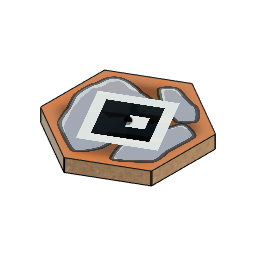
TABLE_2022 (Autodesk Fusion 360 archive; units mm, degrees)
design "EchantillonBleu"
Autodesk Fusion 360 part; units mm, degrees
sketch "Sketch1" plane through (0, 0, 0) normal (0, 0, 1) x (1, 0, 0)
  line L0 (64.9519, 37.5) -> (0, 75)
  line L1 (0, 75) -> (-64.9519, 37.5)
  line L2 (-64.9519, 37.5) -> (-64.9519, -37.5)
  line L3 (-64.9519, -37.5) -> (0, -75)
  line L4 (0, -75) -> (64.9519, -37.5)
  line L5 (64.9519, -37.5) -> (64.9519, 37.5)
  dimension "d3" = 75
  constraint vertical L5
  measures "d3" distance of L0.end origin
extrude "Extrude1" add sketch "Sketch1" along normal blind 15
fillet "Congé1" radius 1 6 edges at (-64.9519, -37.5, 7.5) (0, -75, 7.5) (64.9519, -37.5, 7.5) (64.9519, 37.5, 7.5) (0, 75, 7.5) (-64.9519, 37.5, 7.5)
sketch "Esquisse2" plane through (0, 0, 15) normal (0, 0, 1) x (-1, 0, 0)
  arc A0 (64.4519, -37.7887) -> (64.9519, -36.9226) centre (63.9519, -36.9226) ccw
  line L0 (64.9519, -36.9226) -> (64.9519, 36.9226)
  arc A1 (64.9519, 36.9226) -> (64.4519, 37.7887) centre (63.9519, 36.9226) ccw
  line L1 (64.4519, 37.7887) -> (0.5, 74.7113)
  arc A2 (0.5, 74.7113) -> (-0.5, 74.7113) centre (0, 73.8453) ccw
  line L2 (-0.5, 74.7113) -> (-64.4519, 37.7887)
  arc A3 (-64.4519, 37.7887) -> (-64.9519, 36.9226) centre (-63.9519, 36.9226) ccw
  line L3 (-64.9519, 36.9226) -> (-64.9519, -36.9226)
  arc A4 (-64.9519, -36.9226) -> (-64.4519, -37.7887) centre (-63.9519, -36.9226) ccw
  line L4 (-64.4519, -37.7887) -> (-0.5, -74.7113)
  arc A5 (-0.5, -74.7113) -> (0.5, -74.7113) centre (0, -73.8453) ccw
  line L5 (0.5, -74.7113) -> (64.4519, -37.7887)
equation "diaEchantillon = 150 mm"
equation "epEchantillon = 15 mm"
equation "d3 = diaEchantillon / 2"
equation "d4 = epEchantillon"

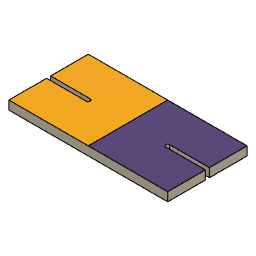
design "MiddleBeaconTop"
Autodesk Fusion 360 part; units mm, degrees
ref_plane "WorkPlane1" through (0, 1000, 0) normal (0, 1, 0) x (0, 0, 1)
sketch "Sketch1" plane through (0, 1000, 0) normal (0, 1, 0) x (1, 0, 0)
  line L0 (-200, -100) -> (200, -100)
  line L1 (200, -100) -> (200, 100)
  line L2 (200, 100) -> (-200, 100)
  line L3 (-200, 100) -> (-200, -100)
  line L4 (-200, -100) -> (200, 100) construction
  line L5 (200, -100) -> (-200, 100) construction
  line L6 (-200, -5) -> (-100, -5)
  arc A0 (-100, -5) -> (-100, 5) centre (-100, 0) ccw
  line L7 (-100, 5) -> (-200, 5)
  arc A1 (-200, 5) -> (-200, -5) centre (-200, 0) ccw
  line L8 (-200, 0) -> (-100, 0) construction
  line L9 (200, 5) -> (100, 5)
  arc A2 (100, 5) -> (100, -5) centre (100, 0) ccw
  line L10 (100, -5) -> (200, -5)
  arc A3 (200, -5) -> (200, 5) centre (200, 0) ccw
  line L11 (200, 0) -> (100, 0) construction
  dimension "d2" = 400
  dimension "d3" = 200
  dimension "d4" = 100
  dimension "d5" = 5
  constraint perpendicular L0 L1
  constraint parallel L0 L2
  constraint parallel L1 L3
  constraint horizontal L0
  constraint coincident L4 origin
  constraint coincident L5 origin
  constraint tangent L6 A0
  constraint tangent A0 L7
  constraint parallel L6 L7
  constraint tangent L7 A1
  constraint tangent L6 A1
  constraint perpendicular L3 L8
  constraint midpoint L3 A1.centre
  constraint tangent L9 A2
  constraint tangent A2 L10
  constraint parallel L9 L10
  constraint tangent L10 A3
  constraint tangent L9 A3
  constraint perpendicular L1 L11
  constraint midpoint L1 A3.centre
  constraint equal A0 A2
  constraint equal L8 L11
  measures "d2" distance of L1.end L2.end
  measures "d3" distance of L0.end L1.end
  measures "d4" distance of A1.centre A0.centre
  measures "d5" radius of A0
extrude "Extrude1" add sketch "Sketch1" against normal blind 22 contours L0 L1 L2 L3 L6 A0 L7 L9 A2 L10
ref_plane "WorkPlane2" through (0, 989, 52.5) normal (1, 0, 0) x (0, 0, 1)
split_face "SplitFace1" 1 faces at (-32.5, 1000, 68.11) by plane through (0, 989, 52.5) normal (1, 0, 0)

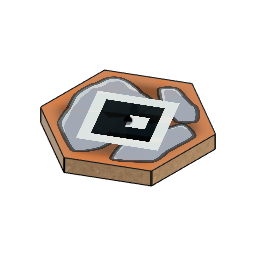
design "EchantillonRouge"
Autodesk Fusion 360 part; units mm, degrees
sketch "Sketch1" plane through (0, 0, 0) normal (0, 0, 1) x (1, 0, 0)
  line L0 (64.9519, 37.5) -> (0, 75)
  line L1 (0, 75) -> (-64.9519, 37.5)
  line L2 (-64.9519, 37.5) -> (-64.9519, -37.5)
  line L3 (-64.9519, -37.5) -> (0, -75)
  line L4 (0, -75) -> (64.9519, -37.5)
  line L5 (64.9519, -37.5) -> (64.9519, 37.5)
  dimension "d3" = 75
  constraint vertical L5
  measures "d3" distance of L0.end origin
extrude "Extrude1" add sketch "Sketch1" along normal blind 15
fillet "Congé1" radius 1 6 edges at (-64.9519, -37.5, 7.5) (0, -75, 7.5) (64.9519, -37.5, 7.5) (64.9519, 37.5, 7.5) (0, 75, 7.5) (-64.9519, 37.5, 7.5)
sketch "Esquisse2" plane through (0, 0, 15) normal (0, 0, 1) x (-1, 0, 0)
  arc A0 (64.4519, -37.7887) -> (64.9519, -36.9226) centre (63.9519, -36.9226) ccw
  line L0 (64.9519, -36.9226) -> (64.9519, 36.9226)
  arc A1 (64.9519, 36.9226) -> (64.4519, 37.7887) centre (63.9519, 36.9226) ccw
  line L1 (64.4519, 37.7887) -> (0.5, 74.7113)
  arc A2 (0.5, 74.7113) -> (-0.5, 74.7113) centre (0, 73.8453) ccw
  line L2 (-0.5, 74.7113) -> (-64.4519, 37.7887)
  arc A3 (-64.4519, 37.7887) -> (-64.9519, 36.9226) centre (-63.9519, 36.9226) ccw
  line L3 (-64.9519, 36.9226) -> (-64.9519, -36.9226)
  arc A4 (-64.9519, -36.9226) -> (-64.4519, -37.7887) centre (-63.9519, -36.9226) ccw
  line L4 (-64.4519, -37.7887) -> (-0.5, -74.7113)
  arc A5 (-0.5, -74.7113) -> (0.5, -74.7113) centre (0, -73.8453) ccw
  line L5 (0.5, -74.7113) -> (64.4519, -37.7887)
equation "diaEchantillon = 150 mm"
equation "epEchantillon = 15 mm"
equation "d3 = diaEchantillon / 2"
equation "d4 = epEchantillon"

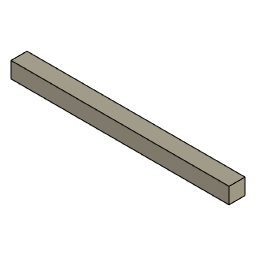
design "BarreSeparation"
Autodesk Fusion 360 part; units mm, degrees
sketch "Sketch1" plane through (0, 0, 0) normal (1, 0, 0) x (0, 1, 0)
  line L0 (11, 0) -> (-11, 0)
  line L1 (-11, 0) -> (-11, 22)
  line L2 (-11, 22) -> (11, 22)
  line L3 (11, 22) -> (11, 0)
  line L4 (11, 0) -> (-11, 22) construction
  line L5 (-11, 0) -> (11, 22) construction
  point P0 (0, 11)
  dimension "d1" = 22
  constraint horizontal L0
  constraint perpendicular L0 L1
  constraint parallel L0 L2
  constraint parallel L1 L3
  constraint coincident L4 P0
  constraint coincident L5 P0
  constraint midpoint origin L0
  constraint equal L2 L3
  measures "d1" distance of L1.end L2.end
extrude "Extrude1" add sketch "Sketch1" along normal blind 300

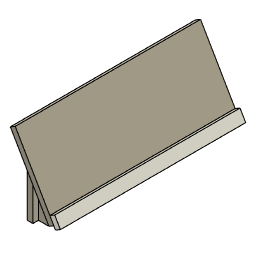
design "Frise"
Autodesk Fusion 360 part; units mm, degrees
sketch "Sketch1" plane through (0, 0, 0) normal (1, 0, 0) x (0, 1, 0)
  line L0 (-600, 70) -> (600, 70)
  line L1 (600, 70) -> (600, 0)
  line L2 (600, 0) -> (-600, 0)
  line L3 (-600, 0) -> (-600, 70)
  dimension "d1" = 70
  dimension "d2" = 1200
  constraint horizontal L0
  constraint vertical L1
  constraint horizontal L2
  constraint vertical L3
  constraint midpoint origin L2
  measures "d1" distance of L0.end L1.end
  measures "d2" distance of L0.start L0.end
extrude "Extrude1" add sketch "Sketch1" against normal blind 22 makes body 1 in component "TERRAIN (A ENLEVER)"
sketch "Sketch2" plane through (0, 0, 0) normal (0, 0, -1) x (1, 0, 0)
  line L0 (0, -600) -> (0, 600)
  line L1 (0, 600) -> (-22, 600)
  line L2 (-22, 600) -> (-22, -600)
  line L3 (-22, -600) -> (0, -600)
  line L4 (-22, 600) -> (978, 600)
  line L5 (978, 600) -> (978, -600)
  line L6 (978, -600) -> (-22, -600)
  line L7 (-22, -600) -> (-22, 600)
  dimension "d5" = 1000
  constraint horizontal L4
  constraint vertical L5
  constraint horizontal L6
  constraint vertical L7
  constraint coincident L1.end L2.start
  constraint coincident L0.start L6
  measures "d5" distance of L1.end L4.end
extrude "Extrude2" add sketch "Sketch2" along normal blind 22 bodies 1 in component "TERRAIN (A ENLEVER)"
sketch "Sketch3" plane through (0, 0, 0) normal (0, 1, 0) x (1, 0, 0)
  line L0 (0, 0) -> (0, -70)
  line L1 (0, -70) -> (40.4145, 0)
  line L2 (40.4145, 0) -> (0, 0)
  line L3 (0, -70) -> (0, -75.899) construction
  line L4 (0, -75.899) -> (0, -118.8533) construction
  line L5 (40.4145, 0) -> (59.4671, -11)
  line L6 (59.4671, -11) -> (-90.5329, -270.8076)
  line L7 (-90.5329, -270.8076) -> (-109.5855, -259.8076)
  line L8 (-109.5855, -259.8076) -> (40.4145, 0)
  line L9 (59.4671, -11) -> (78.5196, -22)
  line L10 (78.5196, -22) -> (62.8696, -49.1066)
  line L11 (62.8696, -49.1066) -> (43.8171, -38.1066)
  line L12 (43.8171, -38.1066) -> (59.4671, -11)
  dimension "d10" = 70
  dimension "d13" = 30
  dimension "d14" = 22
  dimension "d15" = 300
  dimension "d18" = 22
  dimension "d19" = 31.3
  constraint coincident L0.start L2.end
  constraint vertical L0
  constraint perpendicular L0 L2
  constraint parallel L0 L4
  constraint perpendicular L5 L6
  constraint parallel L5 L7
  constraint parallel L6 L8
  constraint perpendicular L1 L5
  constraint perpendicular L9 L10
  constraint parallel L9 L11
  constraint parallel L10 L12
  constraint perpendicular L6 L9
  measures "d10" distance of L0.start L0.end
  measures "d13" angle of L1 L4
  measures "d14" distance of L1.end L5.end
  measures "d15" distance of L5.end L6.end
  measures "d18" distance of L10.end L11.end
  measures "d19" distance of L9.end L10.end
extrude "Extrude1'" add sketch "Sketch3" along normal mid plane 720 separate body contours L1 L5 L6 L7 L8 L12 makes body 2 in component "FRISE"
extrude "Extrude1''" add sketch "Sketch3" along normal mid plane 720 separate body contours L6 L9 L10 L11 L12 makes body 3 in component "BORDURE"
extrude "Extrude1'''" add sketch "Sketch3" along normal blind 22 from surface at -360 separate body contours L0 L1 L2 L8 makes body 4 in component "TRIANGLE_GAUCHE"
extrude "Extrude1''''" add sketch "Sketch3" against normal blind 22 from surface at 360 separate body contours L0 L1 L2 L8 makes body 5 in component "TRIANGLE_DROIT"
extrude "Extrude1'''''" add sketch "Sketch3" along normal mid plane 22 separate body contours L0 L1 L2 L8 makes body 6 in component "TRIANGLE_CENTRE"
sketch "Esquisse1" plane through (0, -360, 0) normal (0, -1, 0) x (1, 0, 0) in component "BORDURE"
  line L0 (62.8696, 49.1066) -> (43.8171, 38.1066)
  line L1 (43.8171, 38.1066) -> (59.4671, 11)
  line L2 (59.4671, 11) -> (78.5196, 22)
  line L3 (78.5196, 22) -> (62.8696, 49.1066)
  line L4 (59.4671, 11) -> (65.8179, 0)
  line L5 (65.8179, 0) -> (84.8705, 11)
  line L6 (84.8705, 11) -> (78.5196, 22)
  line L7 (40.4145, 0) -> (0, 0)
  constraint coincident L1.end L2.start
  constraint perpendicular L2 L4
  constraint perpendicular L1 L5
  constraint coincident L2.end L3.start
  constraint perpendicular L5 L6
  constraint coincident L4.end L7
extrude "Extrusion2" add sketch "Esquisse1" against normal blind 720 contours L2 L4 L5 L6 bodies 3 in component "BORDURE"
sketch "Esquisse1 (2)" plane through (0, -360, 0) normal (0, -1, 0) x (1, 0, 0) in component "TaquetArriere"
  line L0 (40.4145, 0) -> (0, 70)
  line L1 (0, 70) -> (0, 0)
  line L2 (0, 0) -> (40.4145, 0)
  line L3 (-22, 0) -> (-22, 108.1051)
  line L4 (-22, 108.1051) -> (-44, 146.2102)
  line L5 (-44, 146.2102) -> (-44, 0)
  line L6 (-44, 0) -> (-22, 0)
  line L7 (-109.5855, 259.8076) -> (40.4145, 0)
  dimension "d152" = 22
  dimension "d153" = 22
  constraint vertical L3
  constraint parallel L3 L5
  constraint perpendicular L3 L6
  constraint coincident L3.end L7
  constraint coincident L4.end L7
  constraint collinear L2 L6
  measures "d152" distance of L1 L3
  measures "d153" distance of L3.start L5.end
extrude "Extrusion1" add sketch "Esquisse1 (2)" against normal blind 22 separate body contours L3 L4 L5 L6 L7 makes body 7 in component "TaquetArriere"
extrude "Extrusion2'" add 1 faces at (-36.6667, -352.6667, 0) along direction (0, 0, -1) blind 22 on bodies 7 bodies 7 in component "TaquetArriere"
component "TERRAIN (A ENLEVER)" placed x (1, 0, 0) y (0, 1, 0) z (0, 0, 1) at (0, 0, 0)
component "FRISE" placed x (1, 0, 0) y (0, 1, 0) z (0, 0, 1) at (0, 0, 0)
component "BORDURE" placed x (1, 0, 0) y (0, 1, 0) z (0, 0, 1) at (0, 0, 0)
component "TRIANGLE_GAUCHE" placed x (1, 0, 0) y (0, 1, 0) z (0, 0, 1) at (0, 0, 0)
component "TRIANGLE_DROIT" placed x (1, 0, 0) y (0, 1, 0) z (0, 0, 1) at (0, 0, 0)
component "TRIANGLE_CENTRE" placed x (1, 0, 0) y (0, 1, 0) z (0, 0, 1) at (0, 0, 0)
component "TaquetArriere" placed x (1, 0, 0) y (0, 1, 0) z (0, 0, 1) at (0, 0, 0)
component "TaquetArriere" placed x (1, 0, 0) y (0, 1, 0) z (0, 0, 1) at (0, 698, 0)
component "TaquetArriere" placed x (1, 0, 0) y (0, 1, 0) z (0, 0, 1) at (0, 349, 0)
equation "hauteurFrise = 300 mm"
equation "largeurFrise = 720 mm"
equation "angleFrise = 30 deg"
equation "epaisseurFrise = 22 mm"
equation "d13 = angleFrise"
equation "d14 = epaisseurFrise"
equation "d15 = hauteurFrise"
equation "d16 = largeurFrise / 2"
equation "d18 = epaisseurFrise"
equation "d20 = largeurFrise"
equation "d23 = epaisseurFrise"
equation "d26 = -epaisseurFrise"
equation "d28 = epaisseurFrise"
equation "d62 = 180 deg + angleFrise"

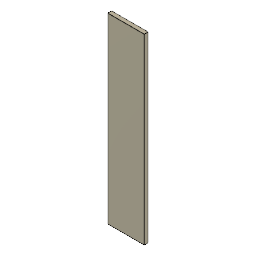
design "MiddleBeaconVertSupport2"
Autodesk Fusion 360 part; units mm, degrees
sketch "Sketch1" plane through (0, 0, 0) normal (0, 0, 1) x (1, 0, 0)
  line L0 (-200, 1000) -> (0, 1000)
  line L1 (0, 1000) -> (0, 0)
  line L2 (0, 0) -> (-200, 0)
  line L3 (-200, 0) -> (-200, 1000)
  dimension "d1" = 1000
  dimension "d2" = 200
  measures "d1" distance of L1.end
extrude "Extrude1" add sketch "Sketch1" along normal mid plane 22

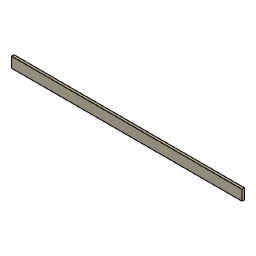
design "BorderSmall"
Autodesk Fusion 360 part; units mm, degrees
sketch "Sketch1" plane through (0, 0, 0) normal (0, 0, 1) x (1, 0, 0)
  line L0 (0, 0) -> (2044, 0)
  line L1 (2044, 0) -> (2044, 92)
  line L2 (2044, 92) -> (0, 92)
  line L3 (0, 92) -> (0, 0)
  dimension "d1" = 2044
  dimension "d2" = 92
  constraint horizontal L0
  constraint vertical L1
  constraint horizontal L2
  constraint vertical L3
  constraint coincident L0.start L3.end
  measures "d1" distance of L0.start L0.end
  measures "d2" distance of L0.start L2.end
extrude "Extrude1" add sketch "Sketch1" along normal blind 22
equation "d1 = 2000 mm + 44 mm"
equation "d2 = 70 mm + 22 mm"
equation "d7 = 22 mm + 400 mm"

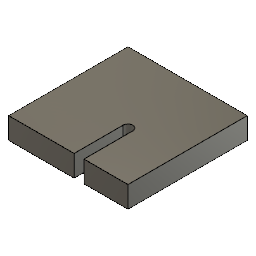
design "EdgeBeacons_Base"
Autodesk Fusion 360 part; units mm, degrees
sketch "Sketch1" plane through (0, 0, 0) normal (0, 1, 0) x (1, 0, 0)
  line L0 (-61, 61) -> (61, 61)
  line L1 (61, 61) -> (61, -61)
  line L2 (-61, -61) -> (-61, 61)
  line L3 (-61, 61) -> (61, -61) construction
  line L4 (16, -61) -> (16, -11)
  arc A0 (16, -11) -> (6, -11) centre (11, -11) ccw
  line L5 (6, -11) -> (6, -61)
  line L6 (11, -61) -> (11, -11) construction
  line L7 (61, -61) -> (16, -61)
  line L8 (6, -61) -> (-61, -61)
  dimension "d1" = 122
  dimension "d4" = 50
  dimension "d5" = 10
  dimension "d6" = 50
  measures "d1" distance of L0.start L0.end
  measures "d4" distance of L6.start A0.centre
  measures "d5" diameter of A0
  measures "d6" distance of L1 L6
extrude "Extrude1" add sketch "Sketch1" along normal blind 22

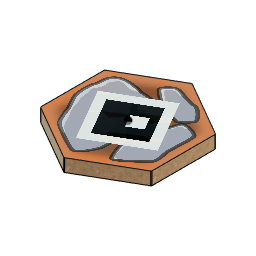
design "EchantillonVert"
Autodesk Fusion 360 part; units mm, degrees
sketch "Sketch1" plane through (0, 0, 0) normal (0, 0, 1) x (1, 0, 0)
  line L0 (64.9519, 37.5) -> (0, 75)
  line L1 (0, 75) -> (-64.9519, 37.5)
  line L2 (-64.9519, 37.5) -> (-64.9519, -37.5)
  line L3 (-64.9519, -37.5) -> (0, -75)
  line L4 (0, -75) -> (64.9519, -37.5)
  line L5 (64.9519, -37.5) -> (64.9519, 37.5)
  dimension "d3" = 75
  constraint vertical L5
  measures "d3" distance of L0.end origin
extrude "Extrude1" add sketch "Sketch1" along normal blind 15
fillet "Congé1" radius 1 6 edges at (-64.9519, -37.5, 7.5) (0, -75, 7.5) (64.9519, -37.5, 7.5) (64.9519, 37.5, 7.5) (0, 75, 7.5) (-64.9519, 37.5, 7.5)
sketch "Esquisse2" plane through (0, 0, 15) normal (0, 0, 1) x (-1, 0, 0)
  arc A0 (64.4519, -37.7887) -> (64.9519, -36.9226) centre (63.9519, -36.9226) ccw
  line L0 (64.9519, -36.9226) -> (64.9519, 36.9226)
  arc A1 (64.9519, 36.9226) -> (64.4519, 37.7887) centre (63.9519, 36.9226) ccw
  line L1 (64.4519, 37.7887) -> (0.5, 74.7113)
  arc A2 (0.5, 74.7113) -> (-0.5, 74.7113) centre (0, 73.8453) ccw
  line L2 (-0.5, 74.7113) -> (-64.4519, 37.7887)
  arc A3 (-64.4519, 37.7887) -> (-64.9519, 36.9226) centre (-63.9519, 36.9226) ccw
  line L3 (-64.9519, 36.9226) -> (-64.9519, -36.9226)
  arc A4 (-64.9519, -36.9226) -> (-64.4519, -37.7887) centre (-63.9519, -36.9226) ccw
  line L4 (-64.4519, -37.7887) -> (-0.5, -74.7113)
  arc A5 (-0.5, -74.7113) -> (0.5, -74.7113) centre (0, -73.8453) ccw
  line L5 (0.5, -74.7113) -> (64.4519, -37.7887)
equation "diaEchantillon = 150 mm"
equation "epEchantillon = 15 mm"
equation "d3 = diaEchantillon / 2"
equation "d4 = epEchantillon"

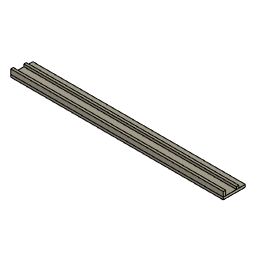
design "SupportCarreFouille"
Autodesk Fusion 360 part; units mm, degrees
sketch "Esquisse1" plane through (0, 0, 0) normal (1, 0, 0) x (0, 1, 0)
  line L0 (0, 0) -> (202, 0)
  line L1 (202, 0) -> (202, 22)
  line L2 (202, 22) -> (0, 22)
  line L3 (0, 22) -> (0, 0)
  line L4 (0, 22) -> (0, 66)
  line L5 (0, 66) -> (22, 66)
  line L6 (22, 66) -> (22, 22)
  line L7 (121, 22) -> (121, 44)
  line L8 (121, 44) -> (143, 44)
  line L9 (143, 44) -> (143, 22)
  dimension "d1" = 22
  dimension "d3" = 22
  dimension "d4" = 44
  dimension "d5" = 22
  dimension "d6" = 22
  dimension "d8" = 59
  dimension "d9" = 180
  constraint coincident L0.start L3.end
  constraint horizontal L0
  constraint perpendicular L0 L1
  constraint perpendicular L1 L2
  constraint perpendicular L0 L3
  constraint perpendicular L2 L4
  constraint perpendicular L3 L5
  constraint coincident L2 L6.end
  constraint perpendicular L2 L6
  constraint coincident L2 L7.start
  constraint perpendicular L2 L7
  constraint perpendicular L7 L8
  constraint coincident L2 L9.end
  constraint perpendicular L2 L9
  measures "d1" distance of L0 L2
  measures "d3" distance of L4.end L5.end
  measures "d4" distance of L2.end L4.end
  measures "d5" distance of L7.end L8.end
  measures "d6" distance of L7.start L7.end
  measures "d8" distance of L1 L9
  measures "d9" distance of L1 L6
extrude "Extrusion1" add sketch "Esquisse1" along normal mid plane 1950 contours L0 L1 L2 L3 makes body 1
extrude "Extrusion2" add sketch "Esquisse1" along normal mid plane 1950 separate body contours L2 L4 L5 L6 makes body 2
extrude "Extrusion3" add sketch "Esquisse1" along normal mid plane 1950 separate body contours L2 L7 L8 L9 makes body 3
equation "d10 = ( 1950 / 2 ) * 1 mm"
equation "d12 = ( 1950 / 2 ) * 1 mm"
equation "d14 = ( 1950 / 2 ) * 1 mm"

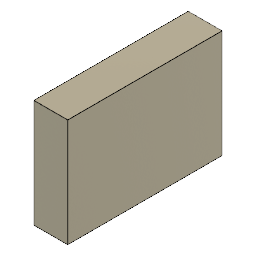
design "EdgeBeacons_SmallBorder"
Autodesk Fusion 360 part; units mm, degrees
sketch "Sketch1" plane through (0, 0, 0) normal (1, 0, 0) x (0, 0, -1)
  line L0 (0, 70) -> (100, 70)
  line L1 (100, 70) -> (100, 0)
  line L2 (100, 0) -> (0, 0)
  line L3 (0, 0) -> (0, 70)
  dimension "d1" = 70
  dimension "d2" = 100
  constraint horizontal L0
  constraint vertical L1
  constraint horizontal L2
  constraint vertical L3
  constraint coincident L2.end L3.start
  measures "d1" distance of L0.start L2.end
  measures "d2" distance of L0.start L0.end
extrude "Extrude1" add sketch "Sketch1" along normal blind 22
equation "d1 = 48 mm + 22 mm"
equation "d2 = 122 mm - 22 mm"

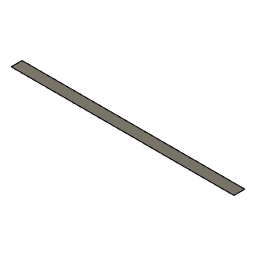
design "PaintExperience"
Autodesk Fusion 360 part; units mm, degrees
sketch "Sketch1" plane through (0, 0, 0) normal (0, 1, 0) x (1, 0, 0)
  line L0 (0, 0) -> (450, 0)
  line L1 (450, 0) -> (450, -22)
  line L2 (450, -22) -> (0, -22)
  line L3 (0, -22) -> (0, 0)
  dimension "d1" = 450
  dimension "d2" = 22
  constraint horizontal L0
  constraint vertical L1
  constraint horizontal L2
  constraint vertical L3
  constraint coincident L0.start L3.end
  measures "d1" distance of L0.start L0.end
  measures "d2" distance of L0.start L2.end
extrude "Extrude1" add sketch "Sketch1" along normal blind 0.1

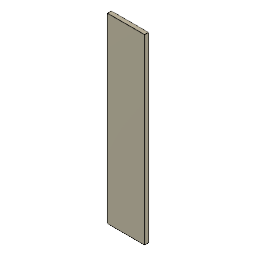
design "MiddleBeaconVertSupport1"
Autodesk Fusion 360 part; units mm, degrees
sketch "Sketch1" plane through (0, 0, 0) normal (0, 0, 1) x (1, 0, 0)
  line L0 (-200, 978) -> (0, 978)
  line L1 (0, 978) -> (0, 0)
  line L2 (0, 0) -> (-200, 0)
  line L3 (-200, 0) -> (-200, 978)
  dimension "d1" = 978
  dimension "d2" = 200
  measures "d1" distance of L1.end
extrude "Extrude1" add sketch "Sketch1" along normal mid plane 22
equation "d1 = 1000 mm - 22 mm"

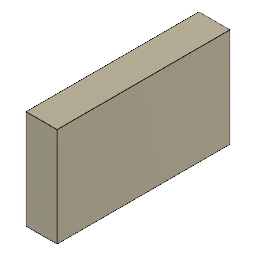
design "EdgeBeacons_LargeBorder"
Autodesk Fusion 360 part; units mm, degrees
sketch "Sketch1" plane through (0, 0, 0) normal (1, 0, 0) x (0, 0, -1)
  line L0 (0, 70) -> (122, 70)
  line L1 (122, 70) -> (122, 0)
  line L2 (122, 0) -> (0, 0)
  line L3 (0, 0) -> (0, 70)
  dimension "d1" = 70
  dimension "d2" = 122
  constraint horizontal L0
  constraint vertical L1
  constraint horizontal L2
  constraint vertical L3
  constraint coincident L2.end L3.start
  measures "d1" distance of L0.start L2.end
  measures "d2" distance of L0.start L0.end
extrude "Extrude1" add sketch "Sketch1" along normal blind 22
equation "d1 = 48 mm + 22 mm"

design "DistributeurCoin"
Autodesk Fusion 360 part; units mm, degrees
sketch "Esquisse1" plane through (0, 0, 0) normal (0, 0, 1) x (1, 0, 0) in component "Bordures (TO REMOVE)"
  line L0 (0, 510) -> (0, 0)
  line L1 (0, 0) -> (510, 0)
  line L2 (510, 0) -> (510, -22)
  line L3 (510, -22) -> (-22, -22)
  line L4 (-22, -22) -> (-22, 510)
  line L5 (0, 510) -> (-22, 510)
  dimension "d1" = 22
  dimension "d2" = 22
  dimension "d3" = 510
  dimension "d4" = 510
  constraint vertical L0
  constraint perpendicular L0 L1
  constraint perpendicular L1 L2
  constraint perpendicular L2 L3
  constraint perpendicular L1 L4
  constraint perpendicular L4 L5
  constraint coincident L0.end L1.start
  measures "d1" distance of L0 L4
  measures "d2" distance of L1 L3
  measures "d3" distance of L0.end L5
  measures "d4" distance of L0.end L2
extrude "Extrusion1" add sketch "Esquisse1" along normal blind 70 makes body 1 in component "Bordures (TO REMOVE)"
sketch "Esquisse1 (2)" plane through (0, 0, 70) normal (0, 0, 1) x (-1, 0, 0) in component "Taquet"
  line L0 (0, 0) -> (0, -510)
  line L1 (0, -510) -> (22, -510)
  line L2 (22, -510) -> (22, 22)
  line L3 (22, 22) -> (-510, 22)
  line L4 (-510, 22) -> (-510, 0)
  line L5 (-510, 0) -> (0, 0)
  line L6 (22, -532) -> (-532, 22)
  line L7 (-532, 22) -> (-331.1817, 22)
  line L8 (22, -532) -> (22, -331.1817)
  line L9 (22, -331.1817) -> (-331.1817, 22)
  dimension "d7" = 142
  constraint coincident L3 L7.end
  constraint perpendicular L4 L7
  constraint coincident L2 L8.end
  constraint perpendicular L1 L8
  constraint parallel L6 L9
  constraint coincident L0.end L6
  constraint coincident L4.end L6
  measures "d7" distance of L6 L9
extrude "Extrusion1'" add sketch "Esquisse1 (2)" along normal blind 22 separate body contours L0 L5 L6 L9 makes body 2 in component "Taquet"
sketch "Esquisse2" plane through (0, 0, 92) normal (0, 0, 1) x (-1, 0, 0) in component "Taquet"
  line L0 (0, -309.1817) -> (-309.1817, 0)
  line L1 (-510, 0) -> (0, -510)
  line L2 (-212.5736, -297.4264) -> (-112.1644, -197.0172) construction
  line L3 (-297.4264, -212.5736) -> (-197.0172, -112.1644) construction
  line L4 (-162.369, -247.2218) -> (27.9921, -475.9614) construction
  line L5 (-475.9614, 27.9921) -> (-247.2218, -162.369) construction
  line L6 (-309.1817, 0) -> (-510, 0)
  line L7 (0, -510) -> (0, -309.1817)
  dimension "d10" = 120
  constraint coincident L1 L2.start
  constraint coincident L0 L2.end
  constraint perpendicular L0 L2
  constraint coincident L1 L3.start
  constraint coincident L0 L3.end
  constraint perpendicular L0 L3
  constraint midpoint L2 L4.start
  constraint midpoint L3 L5.end
  constraint equal L4 L5
  measures "d10" distance of L2 L3
sketch "Esquisse1 (3)" plane through (0, 0, 92) normal (0, 0, 1) x (-1, 0, 0) in component "SupportEchantillon"
  line L0 (0, -309.1817) -> (-309.1817, 0)
  line L1 (-510, 0) -> (0, -510)
  line L2 (-160.8112, -349.1888) -> (-60.402, -248.7797)
  line L3 (-176.3675, -333.6325) -> (-75.9584, -233.2233)
  line L4 (-23.6325, -285.5492) -> (-124.0416, -385.9584)
  line L5 (-139.598, -370.402) -> (-39.1888, -269.9929)
  line L6 (-89.3934, -320.1974) -> (-110.6066, -298.9842) construction
  line L7 (0, 0) -> (0, -510)
  line L8 (0, -510) -> (22, -510)
  line L9 (22, -510) -> (22, 22)
  line L10 (22, 22) -> (-510, 22)
  line L11 (-510, 22) -> (-510, 0)
  line L12 (-510, 0) -> (0, 0)
  line L13 (-309.1817, 0) -> (-510, 0)
  line L14 (0, -510) -> (0, -309.1817)
  point P0 (-100, -309.5908)
  dimension "d11" = 22
  dimension "d12" = 22
  dimension "d13" = 30
  dimension "d14" = 100
  constraint coincident L1 L2.start
  constraint coincident L0 L2.end
  constraint perpendicular L0 L2
  constraint coincident L1 L3.start
  constraint coincident L0 L3.end
  constraint perpendicular L0 L3
  constraint coincident L0 L4.start
  constraint coincident L1 L4.end
  constraint perpendicular L1 L4
  constraint coincident L1 L5.start
  constraint coincident L0 L5.end
  constraint perpendicular L0 L5
  constraint midpoint L5 L6.start
  constraint midpoint L2 L6.end
  constraint midpoint L6 P0
  measures "d11" distance of L4 L5
  measures "d12" distance of L2 L3
  measures "d13" distance of L2 L5
  measures "d14" distance of L7 P0
extrude "Extrusion1''" add sketch "Esquisse1 (3)" along normal blind 200 separate body contours L0 L1 L4 L5 | L0 L1 L2 L3 makes body 3 at (57.1022, 319.0189, 158.6667) makes body 4 at (127.3415, 315.7191, 158.6667) in component "SupportEchantillon"
sketch "Esquisse2 (2)" plane through (-78.6325, 78.6325, 0) normal (0.707107, -0.707107, 0) x (0.707107, 0.707107, 0) in component "SupportEchantillon"
  line L0 (218.6245, 92) -> (360.6245, 92)
  line L1 (360.6245, 92) -> (360.6245, 292)
  line L2 (360.6245, 292) -> (218.6245, 292)
  line L3 (218.6245, 292) -> (218.6245, 92)
  line L4 (344.4587, 92) -> (218.6245, 309.9512)
  line L5 (341.5719, 97) -> (360.6245, 108)
  line L6 (360.6245, 108) -> (349.6245, 127.0526)
  line L7 (349.6245, 127.0526) -> (330.5719, 116.0526)
  line L8 (218.6245, 289.9512) -> (332.9116, 92)
  line L9 (332.9116, 92) -> (341.5719, 97)
  dimension "d17" = 30
  dimension "d18" = 22
  dimension "d19" = 22
  dimension "d20" = 10
  constraint coincident L0 L4.start
  constraint coincident L3 L4.end
  constraint coincident L4 L5.start
  constraint perpendicular L4 L5
  constraint perpendicular L5 L6
  constraint coincident L4 L7.end
  constraint perpendicular L4 L7
  constraint coincident L3 L8.start
  constraint coincident L0 L8.end
  constraint parallel L4 L8
  constraint perpendicular L4 L9
  constraint collinear L5 L9
  constraint coincident L1 L5.end
  measures "d17" angle of L1 L4
  measures "d18" distance of L5.start L5.end
  measures "d19" distance of L5.end L6.end
  measures "d20" distance of L4 L8
extrude "Extrusion2" cut sketch "Esquisse2 (2)" against normal blind 74 contours L0 L4 L9 | L2 L3 L4 L8 L9 | L0 L1 L4 L5 | L4 L5 L6 L7 | L1 L2 L4 L6 L7 bodies 3 4 in component "SupportEchantillon"
sketch "Esquisse3" plane through (204.7222, 204.7222, 167.155) normal (0.612372, 0.612372, 0.5) x (-0.707107, 0.707107, 0) in component "SupportEchantillon"
  line L0 (133.2031, -86.7815) -> (133.2031, 141.7929)
  line L1 (133.2031, 141.7929) -> (111.2031, 141.7929)
  line L2 (111.2031, 141.7929) -> (111.2031, -86.7815)
  line L3 (111.2031, -86.7815) -> (133.2031, -86.7815)
  line L4 (110.7031, 43.2185) -> (185.7031, 43.2185)
  line L5 (185.7031, 43.2185) -> (185.7031, -86.7815)
  line L6 (185.7031, -86.7815) -> (110.7031, -86.7815)
  line L7 (110.7031, -86.7815) -> (110.7031, 43.2185)
  line L8 (111.2031, 27.5057) -> (110.7031, 27.5057) construction
  line L9 (163.2031, 141.7929) -> (163.2031, -86.7815) construction
  line L10 (163.2031, -86.7815) -> (185.2031, -86.7815) construction
  line L11 (185.2031, -86.7815) -> (185.2031, 141.7929) construction
  line L12 (185.2031, 141.7929) -> (163.2031, 141.7929) construction
  line L13 (185.2031, 27.5057) -> (185.7031, 27.5057) construction
  dimension "d23" = 130
  dimension "d24" = 75
  constraint horizontal L4
  constraint perpendicular L4 L5
  constraint perpendicular L0 L6
  constraint perpendicular L4 L7
  constraint collinear L3 L6
  constraint midpoint L2 L8.start
  constraint coincident L7 L8.end
  constraint perpendicular L7 L8
  constraint midpoint L11 L13.start
  constraint coincident L5 L13.end
  constraint perpendicular L5 L13
  constraint equal L8 L13
  measures "d23" distance of L4.start L6.end
  measures "d24" distance of L4.start L4.end
extrude "Extrusion3" add sketch "Esquisse3" along normal blind 10 separate body contours L0 L2 L3 L4 L6 | L0 L4 L5 L6 | L2 L4 L6 L7 makes body 5 in component "SupportEchantillon"
sketch "Esquisse4" plane through (-78.2789, 78.2789, 0) normal (0.707107, -0.707107, 0) x (0.707107, 0.707107, 0) in component "SupportEchantillon"
  line L0 (267.9116, 204.5833) -> (332.9116, 92)
  line L1 (332.9116, 92) -> (341.5719, 97)
  line L2 (341.5719, 97) -> (276.5719, 209.5833)
  line L3 (276.5719, 209.5833) -> (267.9116, 204.5833)
  line L4 (341.5719, 97) -> (360.6245, 108)
  line L5 (360.6245, 108) -> (349.6245, 127.0526)
  line L6 (349.6245, 127.0526) -> (330.5719, 116.0526)
  dimension "d27" = 22
  dimension "d28" = 22
  constraint coincident L1.end L2.start
  constraint perpendicular L2 L4
  constraint perpendicular L4 L5
  constraint coincident L2 L6.end
  constraint perpendicular L2 L6
  measures "d27" distance of L1.end L4.end
  measures "d28" distance of L4.end L5.end
extrude "Extrusion4" add sketch "Esquisse4" against normal up to surface (75 mm away) separate body contours L2 L4 L5 L6 makes body 6 in component "SupportEchantillon"
sketch "Esquisse1 (4)" plane through (0, 0, 92) normal (0, 0, 1) x (-1, 0, 0) in component "SupportStatuette"
  line L0 (-297.4264, -212.5736) -> (-197.0172, -112.1644)
  line L1 (-212.5736, -297.4264) -> (-112.1644, -197.0172)
  line L2 (0, -309.1817) -> (-309.1817, 0)
  line L3 (-510, 0) -> (0, -510)
  line L4 (-197.0172, -112.1644) -> (-212.5736, -127.7208)
  line L5 (-212.5736, -127.7208) -> (-127.7208, -212.5736)
  line L6 (-127.7208, -212.5736) -> (-112.1644, -197.0172)
  point P0 (-112.1644, -197.0172)
  point P1 (-297.4264, -212.5736)
  dimension "d65" = 120
  constraint coincident L0.end L4.start
  constraint perpendicular L2 L4
  constraint coincident P0 L1.end
  constraint perpendicular L2 L6
  measures "d65" distance of L3 L5
extrude "Extrusion1'''" add sketch "Esquisse1 (4)" along normal blind 22 separate body contours L0 L1 L3 L5 makes body 7 in component "SupportStatuette"
sketch "Esquisse3 (2)" plane through (0, 0, 92) normal (0, 0, 1) x (-1, 0, 0) in component "Taquet"
  line L0 (0, -309.1817) -> (-309.1817, 0)
  line L1 (-510, 0) -> (0, -510)
  line L2 (-331.3675, 22.1859) -> (-431.7767, -78.2233)
  line L3 (-246.5147, -62.667) -> (-346.9239, -163.0761)
  line L4 (-197.0172, -112.1644) -> (-297.4264, -212.5736)
  line L5 (-112.1644, -197.0172) -> (-212.5736, -297.4264)
  line L6 (-62.667, -246.5147) -> (-163.0761, -346.9239)
  line L7 (22.1859, -331.3675) -> (-78.2233, -431.7767)
  line L8 (-262.7782, -46.4035) -> (-246.5147, -62.667)
  line L9 (-315.1041, 5.9224) -> (-331.3675, 22.1859)
  line L10 (5.9224, -315.1041) -> (22.1859, -331.3675)
  line L11 (-46.4035, -262.7782) -> (-62.667, -246.5147)
  line L12 (-309.1817, 0) -> (-510, 0)
  line L13 (0, -510) -> (0, -309.1817)
  point P0 (-255, -255)
  point P1 (-315.1041, 5.9224)
  point P2 (-299.5477, -9.6339)
  point P3 (-262.7782, -46.4035)
  point P4 (-278.3345, -30.8472)
  point P5 (5.9224, -315.1041)
  point P6 (-9.6339, -299.5477)
  point P7 (-30.8472, -278.3345)
  point P8 (-46.4035, -262.7782)
  dimension "d33" = 120
  dimension "d34" = 120
  dimension "d35" = 120
  dimension "d36" = 60
  dimension "d37" = 70
  dimension "d38" = 70
  dimension "d40" = 22
  dimension "d41" = 22
  dimension "d42" = 30
  dimension "d43" = 22
  dimension "d44" = 22
  dimension "d45" = 30
  constraint coincident L0 L2.start
  constraint coincident L1 L2.end
  constraint perpendicular L1 L2
  constraint coincident L0 L3.start
  constraint coincident L1 L3.end
  constraint perpendicular L1 L3
  constraint coincident L0 L4.start
  constraint coincident L1 L4.end
  constraint perpendicular L1 L4
  constraint coincident L0 L5.start
  constraint coincident L1 L5.end
  constraint perpendicular L1 L5
  constraint coincident L0 L6.start
  constraint coincident L1 L6.end
  constraint perpendicular L1 L6
  constraint coincident L0 L7.start
  constraint coincident L1 L7.end
  constraint perpendicular L1 L7
  constraint midpoint L1 P0
  constraint coincident L0 P1
  constraint coincident L0 P2
  constraint coincident L0 P3
  constraint coincident L0 P4
  constraint coincident P3 L8.start
  constraint coincident P1 L9.start
  constraint equal L8 L9
  constraint coincident L0 P5
  constraint coincident L0 P6
  constraint coincident L0 P7
  constraint coincident L0 P8
  constraint coincident P5 L10.start
  constraint coincident P8 L11.start
  constraint equal L10 L11
  measures "d33" distance of L2 L3
  measures "d34" distance of L6 L7
  measures "d35" distance of L4 L5
  measures "d36" distance of L4.end P0
  measures "d37" distance of L3.end L4.end
  measures "d38" distance of L5.end L6.end
  measures "d40" distance of P3 P4
  measures "d41" distance of P1 P2
  measures "d42" distance of P2 P4
  measures "d43" distance of P7 P8
  measures "d44" distance of P5 P6
  measures "d45" distance of P6 P7
sketch "Esquisse1 (5)" plane through (0, 0, 70) normal (0, 0, -1) x (1, 0, 0) in component "Planche"
  line L0 (0, -510) -> (510, 0)
  line L1 (309.1817, 0) -> (0, -309.1817)
  line L2 (0, -510) -> (0, 0)
  line L3 (0, 0) -> (510, 0)
  line L4 (510, 0) -> (510, 22)
  line L5 (510, 22) -> (-22, 22)
  line L6 (-22, 22) -> (-22, -510)
  line L7 (-22, -510) -> (0, -510)
  line L8 (0, -478.8873) -> (478.8873, 0)
  line L9 (510, 0) -> (0, -510)
  line L10 (0, -309.1817) -> (0, -510)
  line L11 (510, 0) -> (309.1817, 0)
  dimension "d58" = 22
  constraint coincident L2 L8.start
  constraint coincident L3 L8.end
  constraint parallel L0 L8
  constraint coincident L0.end L3.end
  constraint coincident L0.start L2.start
  measures "d58" distance of L8 L9
extrude "Extrusion1''''" add sketch "Esquisse1 (5)" along normal blind 22 separate body contours L0 L2 L3 L8 L9 L10 L11 makes body 8 in component "Planche"
sketch "Esquisse1 (6)" plane through (0, 0, 92) normal (0, 0, 1) x (-1, 0, 0) in component "Taquet (1)"
  line L0 (0, -309.1817) -> (-309.1817, 0)
  line L1 (-324.738, 15.5563) -> (15.5563, -324.738)
  line L2 (15.5563, -324.738) -> (0, -340.2944)
  line L3 (0, -340.2944) -> (-340.2944, 0)
  line L4 (-340.2944, 0) -> (-324.738, 15.5563)
  line L5 (-309.1817, 0) -> (-510, 0)
  line L6 (0, -510) -> (0, -309.1817)
  dimension "d66" = 22
  constraint parallel L0 L1
  constraint perpendicular L1 L2
  constraint perpendicular L2 L3
  constraint perpendicular L1 L4
  constraint coincident L2.end L6
  constraint coincident L3.end L5
  constraint collinear L0 L1
  measures "d66" distance of L1 L3
extrude "Extrusion1'''''" add sketch "Esquisse1 (6)" along normal blind 22 separate body makes body 9 in component "Taquet (1)"
sketch "Esquisse1 (7)" plane through (0, 0, 92) normal (0, 0, 1) x (-1, 0, 0) in component "Taquet"
  line L0 (0, -309.1817) -> (-309.1817, 0)
  line L1 (-309.1817, 0) -> (-510, 0)
  line L2 (-510, 0) -> (0, -510)
  line L3 (0, -510) -> (0, -309.1817)
  line L4 (-432.2183, 0) -> (0, -432.2183)
  line L5 (-340.2944, 0) -> (0, -340.2944)
  line L6 (-212.5736, -127.7208) -> (-297.4264, -212.5736)
  line L7 (-212.5736, -297.4264) -> (-127.7208, -212.5736)
  point P0 (-120.6497, -311.5685)
  point P1 (-311.5685, -120.6497)
  dimension "d69" = 65
  dimension "d70" = 75
  dimension "d71" = 75
  constraint coincident L4 P0
  constraint coincident L4 P1
  measures "d69" distance of L4 L5
  measures "d70" distance of P1 L6
  measures "d71" distance of P0 L7
component "Bordures (TO REMOVE)" placed x (1, 0, 0) y (0, 1, 0) z (0, 0, 1) at (0, 0, 22)
component "Taquet" placed x (1, 0, 0) y (0, 1, 0) z (0, 0, 1) at (0, 0, 0)
component "SupportEchantillon" placed x (1, 0, 0) y (0, 1, 0) z (0, 0, 1) at (6.9939, 55.0107, 0)
component "SupportEchantillon" placed x (1, 0, 0) y (0, 1, 0) z (0, 0, 1) at (264.6016, -202.5969, 0)
component "SupportStatuette" placed x (1, 0, 0) y (0, 1, 0) z (0, 0, 1) at (0, 0, 0)
component "Planche" placed x (1, 0, 0) y (0, 1, 0) z (0, 0, 1) at (0, 0, 0)
component "Taquet (1)" placed x (1, 0, 0) y (0, 1, 0) z (0, 0, 1) at (0, 0, 0)
equation "d2 = d1"
equation "d4 = d3"
equation "d7 = 120 mm + 22 mm"
equation "d19 = d18"
equation "d28 = d27"
equation "d36 = d35 / 2"
equation "d41 = d40"
equation "d44 = d43"
equation "d69 = ( 130 / 2 ) * 1 mm"
equation "d70 = ( 150 / 2 ) * 1 mm"
equation "d71 = ( 150 / 2 ) * 1 mm"

design "ExperimentZone"
Autodesk Fusion 360 part; units mm, degrees
sketch "Sketch2" plane through (0, 0, 0) normal (0, 1, 0) x (1, 0, 0)
  line L0 (-225, 200) -> (225, 200)
  line L1 (225, 200) -> (225, 0)
  line L2 (225, 0) -> (-225, 0)
  line L3 (-225, 0) -> (-225, 200)
  circle A0 centre (0, 100) radius 5
  line L4 (5, 100) -> (5, 200)
  line L5 (-5, 100) -> (-5, 200)
  dimension "d19" = 450
  dimension "d20" = 200
  dimension "d21" = 225
  dimension "d22" = 10
  dimension "d23" = 100
  dimension "d24" = 225
  constraint horizontal L0
  constraint vertical L1
  constraint horizontal L2
  constraint vertical L3
  constraint coincident L2 origin
  constraint coincident A0 L4.start
  constraint coincident L0 L4.end
  constraint tangent A0 L4
  constraint perpendicular L0 L4
  constraint coincident A0 L5.start
  constraint coincident L0 L5.end
  constraint tangent A0 L5
  constraint perpendicular L0 L5
  measures "d19" distance of L1 L3
  measures "d20" distance of L0 L2
  measures "d21" distance of L3 origin
  measures "d22" diameter of A0
  measures "d23" distance of L0 A0.centre
  measures "d24" distance of L3 A0.centre
extrude "Extrude2" add sketch "Sketch2" against normal blind 22 contours L0 L1 L2 L3 A0 L4 L5
equation "d21 = d19 / 2"
equation "d24 = d21"

design "Ground"
Autodesk Fusion 360 part; units mm, degrees
sketch "Sketch1" plane through (0, 0, 0) normal (0, 1, 0) x (1, 0, 0)
  line L0 (0, 0) -> (3000, 0)
  line L1 (3000, 0) -> (3000, -2000)
  line L2 (3000, -2000) -> (0, -2000)
  line L3 (0, -2000) -> (0, 0)
  dimension "d1" = 2000
  dimension "d2" = 3000
  constraint horizontal L0
  constraint vertical L1
  constraint horizontal L2
  constraint vertical L3
  constraint coincident L0.start L3.end
  measures "d1" distance of L0.start L2.end
  measures "d2" distance of L0.start L0.end
extrude "Extrude1" add sketch "Sketch1" along normal blind 22
equation "z = "

design "BorderLong"
Autodesk Fusion 360 part; units mm, degrees
sketch "Sketch1" plane through (0, 0, 0) normal (0, 0, 1) x (1, 0, 0)
  line L0 (0, 0) -> (3000, 0)
  line L1 (3000, 0) -> (3000, 92)
  line L2 (3000, 92) -> (0, 92)
  line L3 (0, 92) -> (0, 0)
  dimension "d1" = 3000
  dimension "d2" = 92
  constraint horizontal L0
  constraint vertical L1
  constraint horizontal L2
  constraint vertical L3
  constraint coincident L0.start L3.end
  measures "d1" distance of L0.start L0.end
  measures "d2" distance of L0.start L2.end
extrude "Extrude1" add sketch "Sketch1" along normal blind 22
equation "d2 = 70 mm + 22 mm"
